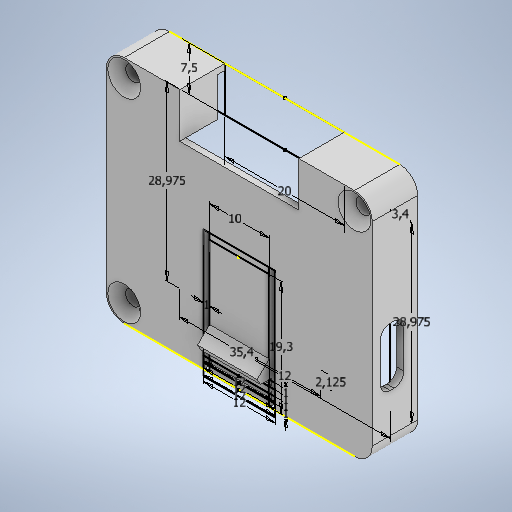
# Autodesk Inventor part: akkum_cup_pd
Saved by Autodesk Inventor 2025 (Build 290162000, 162)
## iProperties
Created: 2026-10-29
Part Number: akkum_cup_pd
Material: Типовые
Document SubType Name: Modeling
Designer: Leva
Density: 1 g/cm^3
Appearance: По умолчанию
Author: Leva
Autodesk Inventor part; units mm, degrees
ref_plane "YZ Plane" through (0, 0, 0) normal (1, 0, 0) x (0, 1, 0)
ref_plane "XZ Plane" through (0, 0, 0) normal (0, 1, 0) x (-1, 0, 0)
ref_plane "XY Plane" through (0, 0, 0) normal (0, 0, 1) x (1, 0, 0)
sketch "Эскиз1" plane through (0, 0, 0) normal (0, 0, 1) x (1, 0, 0)
  line L0 (2, -17.15) -> (2, -17.55) construction
  arc A0 (1, -18.55) -> (2, -17.55) centre (1, -17.55) ccw construction
  line L1 (1, -18.55) -> (-1, -18.55) construction
  arc A1 (-2, -17.55) -> (-1, -18.55) centre (-1, -17.55) ccw construction
  line L2 (-2, -17.55) -> (-2, -17.15) construction
  arc A2 (-1, -16.15) -> (-2, -17.15) centre (-1, -17.15) ccw construction
  line L3 (-1, -16.15) -> (1, -16.15) construction
  arc A3 (2, -17.15) -> (1, -16.15) centre (1, -17.15) ccw construction
  line L4 (2, 17.55) -> (2, 17.15) construction
  arc A4 (1, 16.15) -> (2, 17.15) centre (1, 17.15) ccw construction
  line L5 (1, 16.15) -> (-1, 16.15) construction
  arc A5 (-2, 17.15) -> (-1, 16.15) centre (-1, 17.15) ccw construction
  line L6 (-2, 17.15) -> (-2, 17.55) construction
  arc A6 (-1, 18.55) -> (-2, 17.55) centre (-1, 17.55) ccw construction
  line L7 (-1, 18.55) -> (1, 18.55) construction
  arc A7 (2, 17.55) -> (1, 18.55) centre (1, 17.55) ccw construction
  line L8 (-18.55, 1.3678) -> (-14.15, 1.3678) construction
  arc A8 (-1.3678, 14.15) -> (-14.15, 1.3678) centre (-9.15, 9.15) ccw construction
  line L9 (1.3678, 14.15) -> (-1.3678, 14.15) construction
  arc A9 (14.15, 1.3678) -> (1.3678, 14.15) centre (9.15, 9.15) ccw construction
  line L10 (14.15, 1.3678) -> (18.55, 1.3678) construction
  line L11 (18.55, 2) -> (18.55, 1.3678) construction
  arc A10 (21.05, 2) -> (18.55, 2) centre (19.8, 2) ccw construction
  line L12 (21.05, -2) -> (21.05, 2) construction
  arc A11 (18.55, -2) -> (21.05, -2) centre (19.8, -2) ccw construction
  line L13 (18.55, -1.3678) -> (18.55, -2) construction
  line L14 (18.55, -1.3678) -> (14.15, -1.3678) construction
  arc A12 (1.3678, -14.15) -> (14.15, -1.3678) centre (9.15, -9.15) ccw construction
  line L15 (-1.3678, -14.15) -> (1.3678, -14.15) construction
  arc A13 (-14.15, -1.3678) -> (-1.3678, -14.15) centre (-9.15, -9.15) ccw construction
  line L16 (-14.15, -1.3678) -> (-18.55, -1.3678) construction
  line L17 (-18.55, -2) -> (-18.55, -1.3678) construction
  arc A14 (-21.05, -2) -> (-18.55, -2) centre (-19.8, -2) ccw construction
  line L18 (-21.05, 2) -> (-21.05, -2) construction
  arc A15 (-18.55, 2) -> (-21.05, 2) centre (-19.8, 2) ccw construction
  line L19 (-18.55, 1.3678) -> (-18.55, 2) construction
  arc A16 (19.3, -19.3) -> (22.3, -16.3) centre (19.3, -16.3) ccw projected
  line L20 (22.3, 16.3) -> (22.3, -16.3) projected
  arc A17 (22.3, 16.3) -> (19.3, 19.3) centre (19.3, 16.3) ccw projected
  line L21 (-19.3, 19.3) -> (19.3, 19.3) projected
  arc A18 (-19.3, 19.3) -> (-22.3, 16.3) centre (-19.3, 16.3) ccw projected
  line L22 (-22.3, -16.3) -> (-22.3, 16.3) projected
  arc A19 (-22.3, -16.3) -> (-19.3, -19.3) centre (-19.3, -16.3) ccw projected
  line L23 (19.3, -19.3) -> (-19.3, -19.3) projected
  circle A20 centre (19.3, -16.3) radius 1.8 construction
  circle A21 centre (-19.3, -16.3) radius 1.8 construction
  circle A22 centre (-19.3, 16.3) radius 1.8 construction
  circle A23 centre (19.3, 16.3) radius 1.8 construction
  circle A24 centre (-19.3, 16.3) radius 1.25
  circle A25 centre (19.3, 16.3) radius 1.25
  circle A26 centre (-19.3, -16.3) radius 1.25
  circle A27 centre (19.3, -16.3) radius 1.25
  point P0 (0, 0)
  dimension "d0" = 2.5
  dimension "d3" = 38.6
  dimension "d6" = 32.6
  constraints: 4 centre point, 1 coincident, 1 horizontal, 1 vertical, 6 other
  measures "d0" diameter of A24
  measures "d3" distance of A24.centre A25.centre
  measures "d6" distance of A24.centre A26.centre
extrude "Выдавливание1" add sketch "Эскиз1" along normal blind 7.6 contours L23 A19 L22 A18 L21 A17 L20 A16 | A27
sketch "Эскиз2" plane through (0, 0, 0) normal (0, 0, -1) x (-1, 0, 0)
  line L0 (17.3, 16.3) -> (17.3, -17.1) construction
  line L1 (15.3, -19.1) -> (-15.3, -19.1) construction
  line L2 (-17.3, -17.1) -> (-17.3, 16.3) construction
  line L3 (19.3, 19.3) -> (-19.3, 19.3) construction
  line L4 (17.3, 16.3) -> (17.3, 19.3) construction
  line L5 (17.3, 19.3) -> (17.7, 19.3)
  arc A0 (22.3, 16.3) -> (19.3, 19.3) centre (19.3, 16.3) ccw projected
  line L6 (19.3, 19.3) -> (-19.3, 19.3) projected
  arc A1 (-19.3, 19.3) -> (-22.3, 16.3) centre (-19.3, 16.3) ccw projected
  line L7 (-22.3, 16.3) -> (-22.3, -16.3) projected
  arc A2 (-22.3, -16.3) -> (-19.3, -19.3) centre (-19.3, -16.3) ccw projected
  line L8 (-19.3, -19.3) -> (19.3, -19.3) projected
  arc A3 (19.3, -19.3) -> (22.3, -16.3) centre (19.3, -16.3) ccw projected
  line L9 (22.3, -16.3) -> (22.3, 16.3) projected
  line L10 (21.05, 2) -> (21.05, -2) projected
  circle A4 centre (19.3, 16.3) radius 1.25
  circle A5 centre (-19.3, 16.3) radius 1.25
  circle A6 centre (-19.3, -16.3) radius 1.25 construction
  circle A7 centre (19.3, -16.3) radius 1.25
  line L11 (10, 19.3) -> (-10, 19.3)
  line L12 (-10, 19.3) -> (-10, 11.8)
  line L13 (-10, 11.8) -> (10, 11.8)
  line L14 (10, 11.8) -> (10, 19.3)
  line L15 (17.7, 19.3) -> (17.7, -19.3)
  line L16 (17.7, -19.3) -> (-17.7, -19.3)
  line L17 (-17.7, -19.3) -> (-17.7, 18.3)
  line L18 (-17.7, 18.3) -> (17.7, 18.3)
  line L19 (17.1714, 11.3) -> (17.7, 11.3) construction
  line L20 (17.7, 11.3) -> (17.7, 11.8) construction
  line L21 (17.7, 11.8) -> (17.1714, 11.8) construction
  line L22 (17.1714, 11.8) -> (17.1714, 11.3) construction
  line L23 (17.7, 11.8) -> (53.1, 11.8) construction
  line L24 (17.7, 11.8) -> (-17.7, 11.8)
  line L25 (17.1714, -16.6747) -> (17.7, -16.6747) construction
  line L26 (17.7, -16.6747) -> (17.7, -17.1747) construction
  line L27 (17.7, -17.1747) -> (17.1714, -17.1747) construction
  line L28 (17.1714, -17.1747) -> (17.1714, -16.6747) construction
  line L29 (17.7, -17.1747) -> (-17.7, -17.1747)
  line L30 (17.7, -17.1747) -> (53.1, -17.1747) construction
  line L31 (-19.3, 17.55) -> (-17.7, 17.55)
  line L32 (-19.3, 15.05) -> (-17.7, 15.05)
  line L33 (19.3, -17.55) -> (17.7, -17.55)
  line L34 (19.3, -15.05) -> (17.7, -15.05)
  line L35 (19.3, 17.55) -> (17.7, 17.55)
  line L36 (19.3, 15.05) -> (17.7, 15.05)
  line L37 (21.05, 2) -> (21.05, -2) construction
  arc A8 (21.05, 2) -> (18.55, 2) centre (19.8, 2) ccw projected
  arc A9 (18.55, -2) -> (21.05, -2) centre (19.8, -2) ccw projected
  line L38 (19.8, 3.25) -> (17.7, 3.25)
  line L39 (19.8, -3.25) -> (17.7, -3.25)
  line L40 (-17.7, 11.8) -> (-21.1, 11.8)
  line L41 (-17.7, 11.8) -> (-14.3, 11.8) construction
  line L42 (-21.1, 11.8) -> (-21.1, -17.1747)
  line L43 (-21.1, 11.8) -> (7.8747, 11.8) construction
  line L44 (-21.1, -17.1747) -> (-17.7, -17.1747)
  line L45 (6, -18.3) -> (-6, -18.3)
  line L46 (-6, -18.3) -> (-6, -19.3)
  line L47 (-6, -19.3) -> (6, -19.3)
  line L48 (6, -19.3) -> (6, -18.3)
  point P0 (0, 0)
  point P1 (0, 19.3)
  point P2 (10, 18.3)
  point P3 (-10, 18.3)
  point P4 (0, -19.3)
  dimension "d11" = 0.4
  dimension "d17" = 2.5
  dimension "d18" = 2.5
  dimension "d19" = 2.5
  dimension "d20" = 2.5
  dimension "d21" = 20
  dimension "d22" = 7.5
  dimension "d23" = 35.4
  dimension "d24" = 37.6
  dimension "d25" = 90
  dimension "d26" = 0.5
  dimension "d28" = 0.5
  dimension "d29" = 180
  dimension "d30" = 3.4
  dimension "d31" = 180
  dimension "d32" = 90
  dimension "d63" = 12
  dimension "d64" = 1
  constraints: 76 end point, 15 horizontal, 9 parallel, 9 perpendicular, 9 point on line, 8 point on circle, 8 tangent, 4 centre point, 4 coincident, 4 midpoint, 3 equal length, 1 collinear, 14 other
  measures "d11" distance of L4.end L5.end
  measures "d17" diameter of A4
  measures "d18" diameter of A5
  measures "d19" diameter of A6
  measures "d20" diameter of A7
  measures "d21" distance of L13.end L12.end
  measures "d22" distance of L12.end L11.end
  measures "d23" distance of L16.start L16.end
  measures "d24" distance of L16.end L17.end
  measures "d25" angle of L16 L17
  measures "d26" distance of L20.end L19.end
  measures "d28" distance of L25.end L26.end
  measures "d29" angle of L29 L30
  measures "d30" distance of L24.end L40.end
  measures "d31" angle of L41 L40
  measures "d32" angle of L42 L43
  measures "d63" distance of L47.end L46.end
  measures "d64" distance of L46.end L45.end
extrude "Выдавливание2" cut sketch "Эскиз2" against normal blind 1.2 contours L15 L24 L14 L18 | L35 A4 L36 L15 | L12 L24 L17 L18 | L24 L15 L29 L17 L13 | L17 L32 A5 L31 | L8 L48 L45 L46 L17 L29 L15 | L8 L46 L45 L48 | L15 L34 A7 L33
sketch "Эскиз3" plane through (0, 0, 0) normal (0, 0, -1) x (-1, 0, 0)
  line L0 (-10, 19.3) -> (10, 19.3)
  line L1 (10, 19.3) -> (10, 11.8)
  line L2 (10, 11.8) -> (-10, 11.8)
  line L3 (-10, 11.8) -> (-10, 19.3)
  line L4 (-19.3, 19.3) -> (19.3, 19.3) projected
  line L5 (-17.7, 11.8) -> (17.7, 11.8)
  line L6 (17.7, 11.8) -> (17.7, -17.175)
  line L7 (17.7, -17.175) -> (-17.7, -17.175)
  line L8 (-17.7, -17.175) -> (-17.7, 11.8)
  line L9 (-17.7, -17.175) -> (-21.1, -17.175)
  line L10 (-21.1, -17.175) -> (-21.1, 11.8)
  line L11 (-21.1, 11.8) -> (-17.7, 11.8)
  line L12 (-17.7, 11.8) -> (-17.7, -17.175)
  line L13 (6, -17.175) -> (-6, -17.175)
  line L14 (-6, -17.175) -> (-6, -19.3)
  line L15 (-6, -19.3) -> (6, -19.3)
  line L16 (6, -19.3) -> (6, -17.175)
  line L17 (17.7, -19.3) -> (-17.7, -19.3) projected
  point P0 (0, 0)
  point P1 (0, 19.3)
  point P2 (0, 11.8)
  point P3 (0, -19.3)
  dimension "d35" = 20
  dimension "d36" = 7.5
  dimension "d37" = 28.975
  dimension "d38" = 35.4
  dimension "d43" = 3.4
  dimension "d44" = 28.975
  dimension "d65" = 12
  dimension "d66" = 2.125
  constraints: 32 end point, 8 parallel, 6 midpoint, 4 horizontal, 4 perpendicular
  measures "d35" distance of L1.end L2.end
  measures "d36" distance of L0.end L1.end
  measures "d37" distance of L5.end L6.end
  measures "d38" distance of L6.end L7.end
  measures "d43" distance of L10.end L11.end
  measures "d44" distance of L9.end L10.end
  measures "d65" distance of L15.end L14.end
  measures "d66" distance of L14.end L13.end
extrude "Выдавливание3" cut sketch "Эскиз3" against normal blind 6.6 contours L2 L5 L6 L7 L8 | L8 L9 L10 L11 | L7 L16 L15 L14
extrude "Выдавливание4" cut sketch "Эскиз3" against normal blind 7.6 contours L0 L1 L2 L3
sketch "Эскиз4" plane through (22.3, -16.3, 0) normal (1, 0, 0) x (0, 0, -1)
  line L0 (-2.7001, 8.2337) -> (-2.7001, 14.6737) projected
  arc A0 (-2.7001, 14.6737) -> (-3.9501, 15.9237) centre (-3.9501, 14.6737) ccw projected
  line L1 (-3.9501, 15.9237) -> (-4.6101, 15.9237) projected
  arc A1 (-4.6101, 15.9237) -> (-5.8601, 14.6737) centre (-4.6101, 14.6737) ccw projected
  line L2 (-5.8601, 14.6737) -> (-5.8601, 8.2337) projected
  line L3 (-3.9501, 6.9837) -> (-4.6101, 6.9837) projected
  arc A2 (-3.9501, 6.9837) -> (-2.7001, 8.2337) centre (-3.9501, 8.2337) ccw projected
  arc A3 (-5.8601, 8.2337) -> (-4.6101, 6.9837) centre (-4.6101, 8.2337) ccw projected
  arc A4 (-2.3001, 14.6737) -> (-3.9501, 16.3237) centre (-3.9501, 14.6737) ccw
  line L4 (-2.3001, 14.6737) -> (-2.3001, 8.2337)
  arc A5 (-3.9501, 6.5837) -> (-2.3001, 8.2337) centre (-3.9501, 8.2337) ccw
  line L5 (-3.9501, 6.5837) -> (-4.6101, 6.5837)
  arc A6 (-6.2601, 8.2337) -> (-4.6101, 6.5837) centre (-4.6101, 8.2337) ccw
  line L6 (-6.2601, 8.2337) -> (-6.2601, 14.6737)
  arc A7 (-4.6101, 16.3237) -> (-6.2601, 14.6737) centre (-4.6101, 14.6737) ccw
  line L7 (-4.6101, 16.3237) -> (-3.9501, 16.3237)
  point P0 (0, 16.3)
  dimension "d45" = 0.4
  constraints: 8 end point, 8 point on circle, 4 centre point, 7 other
  measures "d45" radial gap between concentric circles of A0 A4
extrude "Выдавливание5" cut sketch "Эскиз4" against normal blind 1.2 contours A2 L3 A3 L2 A1 L1 A0 L0 | L4 A5 L5 A6 L6 A7 L7 A4
sketch "Эскиз5" plane through (0, 0, 7.6) normal (0, 0, 1) x (1, 0, 0)
  line L0 (-5, -19.3) -> (5, -19.3)
  line L1 (5, -19.3) -> (5, 0)
  line L2 (5, 0) -> (-5, 0)
  line L3 (-5, 0) -> (-5, -19.3)
  line L4 (-19.3, -19.3) -> (19.3, -19.3) projected
  line L5 (-6, -20.3) -> (6, -20.3)
  line L6 (6, -20.3) -> (6, 1)
  line L7 (6, 1) -> (-6, 1)
  line L8 (-6, 1) -> (-6, -20.3)
  line L9 (-6, -18.3) -> (6, -18.3)
  line L10 (6, -18.3) -> (6, -19.3)
  line L11 (6, -19.3) -> (-6, -19.3)
  line L12 (-6, -19.3) -> (-6, -18.3)
  line L13 (-6, -15.3) -> (6, -15.3)
  line L14 (6, -15.3) -> (6, -16.3)
  line L15 (6, -16.3) -> (-6, -16.3)
  line L16 (-6, -16.3) -> (-6, -15.3)
  line L17 (-6, -16.3) -> (6, -16.3)
  line L18 (6, -16.3) -> (6, -17.3)
  line L19 (6, -17.3) -> (-6, -17.3)
  line L20 (-6, -17.3) -> (-6, -16.3)
  line L21 (-6, -17.3) -> (6, -17.3)
  line L22 (6, -17.3) -> (6, -18.3)
  line L23 (6, -18.3) -> (-6, -18.3)
  line L24 (-6, -18.3) -> (-6, -17.3)
  line L25 (-5, 0) -> (-5, 1)
  line L26 (5, 0) -> (5, 1)
  point P0 (0, 0)
  point P1 (0, -19.3)
  point P2 (0, -19.3)
  point P3 (0, -18.3)
  point P4 (0, -17.3)
  point P5 (0, -16.3)
  point P6 (5, -19.3)
  point P7 (6, -19.3)
  point P8 (-6, -19.3)
  point P9 (-5, -19.3)
  point P10 (-5, -16.3)
  point P11 (5, -16.3)
  point P12 (5, -15.3)
  point P13 (-5, -15.3)
  point P14 (5, -17.3)
  point P15 (-5, -17.3)
  point P16 (-5, -18.3)
  point P17 (5, -18.3)
  dimension "d48" = 19.3
  dimension "d49" = 10
  dimension "d50" = 1
  dimension "d51" = 12
  dimension "d52" = 1
  dimension "d53" = 12
  dimension "d54" = 1
  dimension "d55" = 12
  dimension "d56" = 1
  dimension "d57" = 12
  dimension "d58" = 1
  constraints: 52 end point, 12 parallel, 10 midpoint, 8 perpendicular, 5 horizontal, 2 point on line, 3 other
  measures "d48" distance of L1.end L0.end
  measures "d49" distance of L1.end L2.end
  measures "d50" distance between parallel lines of L3 L8
  measures "d51" distance of L10.end L11.end
  measures "d52" distance of L9.end L10.end
  measures "d53" distance of L14.end L15.end
  measures "d54" distance of L13.end L14.end
  measures "d55" distance of L19.start L20.start
  measures "d56" distance of L17.end L19.start
  measures "d57" distance of L23.start L24.start
  measures "d58" distance of L21.end L23.start
extrude "Выдавливание6" cut sketch "Эскиз5" against normal blind 7.6 contours L4 L8 L9 L3 | L1 L9 L6 L4 | L9 L8 L19 L3 | L1 L19 L6 L9 | L19 L8 L15 L3 | L1 L15 L6 L19 | L15 L8 L13 L3 | L1 L13 L6 L15 | L13 L8 L7 L25 L3 | L1 L26 L7 L6 L13
extrude "Выдавливание7" cut sketch "Эскиз5" against normal blind 0.4 contours L3 L19 L1 L9 | L3 L13 L1 L15
sketch "Эскиз6" plane through (5, -17.175, 6.6) normal (1, 0, 0) x (0, 0, -1)
  line L0 (-0.6, 1.875) -> (-1, 1.875) projected
  line L1 (-1, 1.875) -> (-4, 1.875)
  line L2 (-4, 1.875) -> (-1, 4.875)
  line L3 (-1, -2.125) -> (-1, 18.175) projected
  line L4 (-4, 1.875) -> (0.2426, 1.875) construction
  line L5 (-1, 4.875) -> (-1, 1.875)
  line L6 (-1, 1.875) -> (-3, 1.875)
  line L7 (-3, 1.875) -> (-3, 2.875)
  line L8 (-3, 2.875) -> (-1, 2.875)
  line L9 (-1, 2.875) -> (-1, 1.875)
  line L10 (-3, 2.875) -> (-2.4226, 1.875)
  line L11 (-3, 2.875) -> (-1.8453, 2.875) construction
  point P0 (6.6, 17.175)
  point P1 (-3, 2.875)
  point P2 (-2.4226, 1.875)
  dimension "d67" = 3
  dimension "d68" = 45
  dimension "d69" = 2
  dimension "d70" = 1
  dimension "d71" = 60
  constraints: 20 end point, 4 horizontal, 2 equal length, 2 parallel, 2 point on line, 1 collinear, 1 perpendicular
  measures "d67" distance of L0.end L1.end
  measures "d68" angle of L4 L2
  measures "d69" distance of L7.end L8.end
  measures "d70" distance of L6.end L7.end
  measures "d71" angle of L10 L11
extrude "Выдавливание8" add sketch "Эскиз6" against normal blind 10 contours L1 L10 L8 L3 | L8 L2 L3
chamfer "Фаска1" distance 1.5 angle 45 3 edges at (18.05, 16.3, 7.6) (-20.55, 16.3, 7.6) (-20.55, -16.3, 7.6)
